Autodesk Fusion 360 part; units mm, degrees
(part 2 of 2)
ref_plane "WorkPlane4" through (0, 0, 1231.63) normal (0, 0, 1) x (1, 0, 0) in component "831001 HARDWARE - LOCATING SPIGOT - M6 X Ø8 - STAINLESS"
sketch "SKETCH - SPIGOT THREAD TOP RAIL SPIGOT HIGH X" plane through (0, 0, 1231.63) normal (0, 0, 1) x (1, 0, 0) in component "831001 HARDWARE - LOCATING SPIGOT - M6 X Ø8 - STAINLESS"
  circle A0 centre (1101.74, 824) radius 3
  dimension "d599" = 1101.74
  dimension "d600" = 824
  dimension "d601" = 6
  measures "d599" horizontal distance of origin A0.centre
  measures "d600" vertical distance of origin A0.centre
  measures "d601" diameter of A0
extrude "EXTRUDE - SPIGOT THREAD TOP RAIL SPIGOT HIGH X" add sketch "SKETCH - SPIGOT THREAD TOP RAIL SPIGOT HIGH X" against normal blind 10 separate body makes body 27 in component "831001 HARDWARE - LOCATING SPIGOT - M6 X Ø8 - STAINLESS"
combine "COMBINE - SPIGOT TOP RAIL SPIGOT HIGH X" operation add target body 26 tool bodies 27 in component "831001 HARDWARE - LOCATING SPIGOT - M6 X Ø8 - STAINLESS"
ref_plane "WorkPlane7" through (2.75, 0, 0) normal (1, 0, 0) x (0, 1, 0) in component "838003 HARDWARE - RIVET NUT - M6 - SHEREX CAH3-610-4.2"
sketch "SKETCH - RIVNUT HEAD CENTRE STILE PIN" plane through (2.75, 0, 0) normal (1, 0, 0) x (0, 0, -1) in component "838003 HARDWARE - RIVET NUT - M6 - SHEREX CAH3-610-4.2"
  circle A0 centre (-332.26, 824) radius 6.48
  circle A1 centre (-332.26, 824) radius 3
  dimension "d608" = 824
  dimension "d609" = 332.26
  dimension "d610" = 12.96
  dimension "d611" = 6
  measures "d608" vertical distance of origin A0.centre
  measures "d609" horizontal distance of origin A0.centre
  measures "d610" diameter of A0
  measures "d611" diameter of A1
extrude "EXTRUDE - RIVNUT HEAD CENTRE STILE PIN" add sketch "SKETCH - RIVNUT HEAD CENTRE STILE PIN" against normal blind 0.76 separate body makes body 28 in component "838003 HARDWARE - RIVET NUT - M6 - SHEREX CAH3-610-4.2"
ref_plane "WorkPlane8" through (2.75, 0, 0) normal (1, 0, 0) x (0, 1, 0) in component "838003 HARDWARE - RIVET NUT - M6 - SHEREX CAH3-610-4.2"
sketch "SKETCH - RIVNUT BODY CENTRE STILE PIN" plane through (2.75, 0, 0) normal (1, 0, 0) x (0, 0, -1) in component "838003 HARDWARE - RIVET NUT - M6 - SHEREX CAH3-610-4.2"
  circle A0 centre (-332.26, 824) radius 4.75
  circle A1 centre (-332.26, 824) radius 3
  dimension "d618" = 824
  dimension "d619" = 332.26
  dimension "d620" = 9.5
  dimension "d621" = 6
  measures "d618" vertical distance of origin A0.centre
  measures "d619" horizontal distance of origin A0.centre
  measures "d620" diameter of A0
  measures "d621" diameter of A1
extrude "EXTRUDE - RIVNUT BODY CENTRE STILE PIN" add sketch "SKETCH - RIVNUT BODY CENTRE STILE PIN" along normal blind 10.16 separate body makes body 29 in component "838003 HARDWARE - RIVET NUT - M6 - SHEREX CAH3-610-4.2"
combine "COMBINE - RIVNUT CENTRE STILE PIN" operation add target body 28 tool bodies 29 in component "838003 HARDWARE - RIVET NUT - M6 - SHEREX CAH3-610-4.2"
pattern_linear "PATTERN - RIVNUT - CENTRE STILE PIN" count 3 spacing 339.305 along (0, 0, 1) of bodies 28 makes body 30 at (9.5233, 828.7131, 670.9744) makes body 31 at (9.5233, 828.7131, 1010.2794) in component "838003 HARDWARE - RIVET NUT - M6 - SHEREX CAH3-610-4.2"
component "211202 WALL - PANEL FRAME - BACK LOWER - B2" placed x (1, 0, 0) y (0, 1, 0) z (0, 0, 1) at (0, 0, 0)
component "211402 WALL - SKIN - BACK LOWER - B2" placed x (1, 0, 0) y (0, 1, 0) z (0, 0, 1) at (0, 0, 0)
component "211602 WALL - CAVITY FILL - BACK LOWER - B2" placed x (1, 0, 0) y (0, 1, 0) z (0, 0, 1) at (0, 0, 0)
component "831002 HARDWARE - STOP WASHER - Ø10.5 X Ø20 X 1.5 - AL" placed x (1, 0, 0) y (0, 1, 0) z (0, 0, 1) at (0, 0, 0)
component "838003 HARDWARE - RIVET NUT - M6 - SHEREX CAH3-610-4.2" placed x (1, 0, 0) y (0, 1, 0) z (0, 0, 1) at (0, 0, 0)
component "831001 HARDWARE - LOCATING SPIGOT - M6 X Ø8 - STAINLESS" placed x (1, 0, 0) y (0, 1, 0) z (0, 0, 1) at (0, 0, 0)
equation "pod_w_Ref = 2500 mm" comment "DECIDED: D-01; conventions s4 (X = +-1250)"
equation "pod_d_Ref = 1700 mm" comment "DECIDED: D-01; conventions s4 (Y = +-850)"
equation "pod_h_Ref = 2400 mm" comment "DECIDED: D-21 (room floor to roof skin top)"
equation "glide_h_Ref = 10 mm" comment "ASSUMPTION: layout study inputs.py glide_h"
equation "band_h_Ref = 100 mm" comment "SOURCE: layout study B1 list B-BAND 100x40; inputs.py base_h"
equation "outer_t_Ref = skin_t_Ref + bond_t_Ref + frame_t_Ref" comment "DECIDED: PM ruling 2026-10-31: ACP 3 + bond line 3 + frame 40, walls and ceiling (was 43)"
equation "cav_gap_Ref = 4 mm" comment "DECIDED: D-16, D-42: the gap between the outer panel and the lining cassette in the wall and ceiling stack"
equation "cass_t_Ref = 34 mm" comment "SOURCE: layout study B1 final list L-CASS 34 (tray + 25 gap + felt 9)"
equation "stack_t_Ref = outer_t_Ref + cav_gap_Ref + cass_t_Ref" comment "CALCULATION: D-16, D-42 stack, walls and ceiling: outer panel + cavity gap + cassette (PM ruling 2026-10-31 on outer_t)"
equation "lin_gap_Ref = 4 mm" comment "ASSUMPTION: PM ruling pass C: gap above the upper side linings so they stay floating (= the 4 mm stack gap)"
equation "seam_gap_Ref = 2.26 mm" comment "DECIDED: PM ruling 2026-10-31 (Mechanical Checker F-001, F-005): the Joints Engineer's 2.26 mm at all nine site seam types, set by a metal stop (1.5 stop washer + 0.76 rivnut head; joints register section 2.8)"
equation "wall_z0_Ref = glide_h_Ref + band_h_Ref" comment "CALCULATION: base band top: glides + band"
equation "panel_z0_Ref = wall_z0_Ref + seam_gap_Ref" comment "CALCULATION: walls stand one seam_gap above the band top (joints register 2.8, IF-01)"
equation "back_oh_Ref = pod_h_Ref - outer_t_Ref - seam_gap_Ref - panel_z0_Ref" comment "CALCULATION: PM ruling 2026-10-31 (pass D, F-004): the back outer frames run up to the ceiling frame (pod_h - outer_t), less the seam_gap under it, closing the slot at the back top edge"
equation "back_ph_Ref = ( back_oh_Ref - seam_gap_Ref ) / 2" comment "CALCULATION: D-23: 4 sheets on the back, two equal rows with one seam_gap between them (joints register 2.8); the lower back linings match the lower row, as on the side walls"
equation "half_pw_Ref = ( pod_w_Ref - 2 * outer_t_Ref - 3 * seam_gap_Ref ) / 2" comment "CALCULATION: SKIN width of each back and ceiling panel: two skins and three seam_gap seams between the side frames (F-001, joints register 2.8)"
equation "n_base_bolt_Ref = 4" comment "DECIDED: PM ruling 2026-10-31, J-BASE-01: bolts per panel along the band, evenly spaced"
equation "skin_t_Ref = 3 mm" comment "DECIDED: ACP skin, walls and ceiling (D-16; PM ruling 2026-10-31 on outer_t)"
equation "bond_t_Ref = 3 mm" comment "DECIDED: bond line between the ACP and the frame (PM ruling 2026-10-31 on outer_t)"
equation "frame_t_Ref = 40 mm" comment "DECIDED: aluminium frame tube depth, walls and ceiling (PM ruling 2026-10-31 on outer_t)"
equation "close_gap_Ref = 5.5 mm" comment "DECIDED: PM ruling 2026-10-31 (joints register, F-011/F-012): frame gap at the closing seams B1-B2, B3-B4 and C1-C2, which have no hard stop (slotted holes, thicker gasket)"
equation "half_fw_Ref = ( pod_w_Ref - 2 * outer_t_Ref - 2 * seam_gap_Ref - close_gap_Ref ) / 2" comment "CALCULATION: FRAME width of each back and ceiling panel: the skins overhang their frames by half_pw - half_fw at the closing seam (PM ruling 2026-10-31)"
equation "bolt_edge_inset_Ref = 220 mm" comment "DECIDED: PM ruling 2026-10-31: on every bolted edge the end bolts sit this far in from each panel end (the FRAME end, where the bolts go), the rest evenly spaced"
equation "spigot_inset_Ref = 100 mm" comment "DECIDED: PM ruling 2026-10-31: locating spigots this far in from each panel end (round hole at one end, slot at the other)"
equation "pod_w = pod_w_Ref" comment "LINKED: pod_w_Ref, derived from 100000_P04_POD-SKELETON_CAD v4 (skeleton is the single source)"
equation "pod_d = pod_d_Ref" comment "LINKED: pod_d_Ref, derived from 100000_P04_POD-SKELETON_CAD v4 (skeleton is the single source)"
equation "pod_h = pod_h_Ref" comment "LINKED: pod_h_Ref, derived from 100000_P04_POD-SKELETON_CAD v4 (skeleton is the single source)"
equation "panel_z0 = panel_z0_Ref" comment "LINKED: panel_z0_Ref, derived from 100000_P04_POD-SKELETON_CAD v4 (skeleton is the single source)"
equation "back_ph = back_ph_Ref" comment "LINKED: back_ph_Ref, derived from 100000_P04_POD-SKELETON_CAD v4 (skeleton is the single source)"
equation "back_oh = back_oh_Ref" comment "LINKED: back_oh_Ref, derived from 100000_P04_POD-SKELETON_CAD v4 (skeleton is the single source)"
equation "half_pw = half_pw_Ref" comment "LINKED: half_pw_Ref, derived from 100000_P04_POD-SKELETON_CAD v4 (skeleton is the single source)"
equation "half_fw = half_fw_Ref" comment "LINKED: half_fw_Ref, derived from 100000_P04_POD-SKELETON_CAD v4 (skeleton is the single source)"
equation "close_gap = close_gap_Ref" comment "LINKED: close_gap_Ref, derived from 100000_P04_POD-SKELETON_CAD v4 (skeleton is the single source)"
equation "stack_t = stack_t_Ref" comment "LINKED: stack_t_Ref, derived from 100000_P04_POD-SKELETON_CAD v4 (skeleton is the single source)"
equation "outer_t = outer_t_Ref" comment "LINKED: outer_t_Ref, derived from 100000_P04_POD-SKELETON_CAD v4 (skeleton is the single source)"
equation "cass_t = cass_t_Ref" comment "LINKED: cass_t_Ref, derived from 100000_P04_POD-SKELETON_CAD v4 (skeleton is the single source)"
equation "lin_gap = lin_gap_Ref" comment "LINKED: lin_gap_Ref, derived from 100000_P04_POD-SKELETON_CAD v4 (skeleton is the single source)"
equation "seam_gap = seam_gap_Ref" comment "LINKED: seam_gap_Ref, derived from 100000_P04_POD-SKELETON_CAD v4 (skeleton is the single source)"
equation "skin_t = skin_t_Ref" comment "LINKED: skin_t_Ref, derived from 100000_P04_POD-SKELETON_CAD v4 (skeleton is the single source)"
equation "bond_t = bond_t_Ref" comment "LINKED: bond_t_Ref, derived from 100000_P04_POD-SKELETON_CAD v4 (skeleton is the single source)"
equation "bolt_edge_inset = bolt_edge_inset_Ref" comment "LINKED: bolt_edge_inset_Ref, derived from 100000_P04_POD-SKELETON_CAD v4 (skeleton is the single source)"
equation "spigot_inset = spigot_inset_Ref" comment "LINKED: spigot_inset_Ref, derived from 100000_P04_POD-SKELETON_CAD v4 (skeleton is the single source)"
equation "n_base_bolt = n_base_bolt_Ref" comment "LINKED: n_base_bolt_Ref, derived from 100000_P04_POD-SKELETON_CAD v4 (skeleton is the single source)"
equation "tube_w = 20 mm" comment "CONFIRMED: D-34, D-54: aluminium tube 20 x 40 x 1.2; the 20 mm face carries the skin, so the 40 mm runs through the wall (outer_t = ACP 3 + frame 40). The joint register may turn it for the bond width (HOLD)"
equation "tube_d = outer_t - skin_t - bond_t" comment "CALCULATION: frame depth = outer panel 46 - skin 3 - bond 3 = 40 (D-34)"
equation "tube_t = 1.2 mm" comment "CONFIRMED: D-34, D-54, D-85: perimeter members (rails, front and back stiles) keep the 1.2 mm wall; they carry the rivnuts (grip check passed)"
equation "stud_t = 1.0 mm" comment "CONFIRMED: D-85 (weight): intermediate studs at a 1.0 mm wall; they carry no rivnut, only the skin's bond line"
equation "stile_pitch_max = 400 mm" comment "CONFIRMED: D-16, D-34: members 400 mm apart or less, to keep the ACP flat"
equation "skin_setback = 0 mm" comment "ASSUMPTION: skin edge set back from the frame's top and bottom edges: 0, so the outside reveal equals the 2.26 seam gap (D-23: crisp, aligned reveals; joints register 2.8 leaves the setback to the WALL drawing)"
equation "fill_t = tube_d" comment "CALCULATION: 40 mm PET fill fills the frame depth (D-34; layout study 40 mm)"
equation "bolt_d = 7 mm" comment "CONFIRMED: PM ruling on F-009: bolt holes 7.0 (0.51 float), position tolerance 0.4 (+-0.2) from the spigot hole, CNC or drill jig (joints register FR-02)"
equation "access_d = 19 mm" comment "CALCULATION: register FR-03: passes the 18 mm head washer (ISO 7093-1, R-J10), the M6 head and the 5 mm key; holds the grommet retainer (H-02)"
equation "bolt_line_y = pod_d / 2 - skin_t - bond_t - tube_d / 2" comment "CONFIRMED: J-WALL-02 bolt line on the back panel's tube centre, Y 824 (joints register R-J15, FR-07)"
equation "rivnut_d = 9.53 mm" comment "SOURCE: Sherex CAH3-610-4.2 hole 9.53 +0.10 (HW-SEL A5; register H-03)"
equation "spigot_d = 8.5 mm" comment "ASSUMPTION: register FR-05: hole for the 8 mm locating spigot H-05"
equation "spigot_slot = 14 mm" comment "ASSUMPTION: register FR-05: slot length for the second spigot"
equation "spigot_edge = spigot_inset" comment "CALCULATION: the skeleton's spigot_inset: spigots 100 from each end of the edge (PM ruling 2026-10-31, R-J13)"
equation "bolt_edge = bolt_edge_inset" comment "CALCULATION: the skeleton's bolt_edge_inset: end bolts 220 in from the panel's ends, evenly spaced, every bolt 30 or more from any stile (PM ruling 2026-10-31, R-J14)"
equation "pocket_w = 60 mm" comment "ASSUMPTION: register FR-10: fill left out 60 x 60 next to each bolt for the key"
equation "felt_t = 9 mm" comment "SOURCE: plan VT03-PET 9 mm PET felt; HW-SEL A3; D-31 (the factory's felt)"
equation "tray_t = 0.5 mm" comment "CONFIRMED: D-37: galvanised steel tray 0.5 mm"
equation "tray_h = cass_t" comment "CONFIRMED: PM ruling 2026-10-31 (WALL group, option 1): the wall cassettes use the ceiling's tray, returns the full cassette depth (34) turned in as lips that hold the felt, no ribs; settles H09 for the walls"
equation "lip_w = 12 mm" comment "CONFIRMED: PM ruling 2026-10-31 (WALL group, option 1): 12 mm lips hold the felt edge"
equation "bend_r = tray_t" comment "ASSUMPTION: inside bend radius 1 x t for 0.5 mm DX51D (the sheet metal rule's bend radius is its Thickness); the factory's tooling sets it (guideline 9)"
equation "felt_c = 1 mm" comment "ASSUMPTION: felt edge clearance inside the returns, as the ceiling cassette"
equation "gap_h = tray_h - felt_t - 2 * tray_t" comment "CALCULATION: air gap between the tray base and the felt (24): the acoustic gap (D-17) and the cable path (D-26)"
equation "clip_zone_h = 60 mm" comment "ASSUMPTION: height of each reserved clip zone (H03: no clip named)"
equation "clip_zone_dz = 100 mm" comment "ASSUMPTION: clip zone centre from the cassette's top and bottom edges (H03)"
equation "stopw_od = 20 mm" comment "SOURCE: joints register H-08: stop washer Ø10.5 x Ø20 x 1.5 (PROPOSED part)"
equation "stopw_id = 10.5 mm" comment "SOURCE: joints register H-08"
equation "stopw_t = 1.5 mm" comment "SOURCE: joints register H-08: rivnut head 0.76 + washer 1.5 = the 2.26 stop (R-J5)"
equation "rivnut_head_d = 12.96 mm" comment "SOURCE: Sherex CAH3-610-4.2 head Ø12.96 (joints register H-03, SHX)"
equation "rivnut_head_t = 0.76 mm" comment "SOURCE: Sherex CAH3-610-4.2 head 0.76 ±0.08 (H-03, SHX)"
equation "rivnut_body_d = 9.5 mm" comment "SOURCE: Sherex CAH3-610-4.2 body Ø9.50 max (H-03, SHX)"
equation "rivnut_len = 10.16 mm" comment "SOURCE: Sherex CAH3-610-4.2 installed length 10.16 max under the head (H-03, SHX); the bulge inside the tube is not modelled"
equation "m6_d = 6 mm" comment "CALCULATION: M6 threads shown at their 6 mm major diameter (no modelled thread)"
equation "spigot_pin_d = 8 mm" comment "SOURCE: joints register H-05: Ø8 stainless pin (PROPOSED, assumption sizes)"
equation "spigot_proud = 8 mm" comment "SOURCE: joints register H-05: stands 8 proud (read as: of the joint face)"
equation "spigot_thread_l = 10 mm" comment "ASSUMPTION: M6 thread into the spigot rivnut; H-05 gives no length; 10 stays inside the rivnut's 10.16"
equation "lead_in = 1 mm" comment "SOURCE: joints register 2.10 (R-J9): 1 x 45 degree lead-in on the top edge of each closing-seam face, so the panel beside it drops in past it without catching the bulb seal"
equation "pnl_len = half_pw" comment "CALCULATION: skeleton half_pw: the back panel's skin width (1200.61 on P04)"
equation "frm_len = half_fw" comment "CALCULATION: the skeleton's half_fw, 1198.99: the frame stops close_gap / 2 from X 0 and 1.62 short of its skin (R-J16)"
equation "pnl_h = back_ph" comment "CALCULATION: skeleton back row height (1118.61 on P04)"
equation "frm_h = pnl_h" comment "CALCULATION: the frame fills the row height; the seam gaps are outside it (P04)"
equation "top_h = tube_w" comment "CALCULATION: the back panels' top rails stay 20 x 40 (the ceiling's back member is the 40 x 40, R-J3)"
equation "stile_n_mid = ceil(( frm_len - tube_w ) / stile_pitch_max) - 1" comment "CALCULATION: intermediate stiles so that no stile pitch exceeds stile_pitch_max"
equation "stile_pitch = ( frm_len - tube_w ) / ( stile_n_mid + 1 )" comment "CALCULATION: equal stile pitch, centre to centre"
equation "stile_len = frm_h - 2 * tube_w" comment "CALCULATION: stiles between the full-width rails (butt joints)"
equation "n_len_bolt = n_base_bolt" comment "CALCULATION: the skeleton's n_base_bolt (4): also on the horizontal seam and the ceiling back edge (register 2.9; the skeleton's n_ceil_back_bolt 3 is an old assumption, flagged)"
equation "len_bolt_pitch = ( frm_len - 2 * bolt_edge ) / ( n_len_bolt - 1 )" comment "CALCULATION: 253.00 on P04: 220, 473.00, 725.99, 978.99 from the frame's ends (register 2.9; the skeleton's back_base_pitch uses the 1200.61 skin and gives 253.54, flagged to its owner)"
equation "n_side_jnt = 3" comment "SOURCE: 3 bolts on the back corner and on the closing seam (register 2.9)"
equation "side_jnt_pitch = ( pnl_h - 2 * bolt_edge ) / ( n_side_jnt - 1 )" comment "CALCULATION: 339.31 on P04: 220, 559.31, 898.61 up the 1118.61 edge (register 2.9)"
equation "cass_len = pod_w / 2 - stack_t - seam_gap / 2" comment "ASSUMPTION: PROPOSED (WALL): from the side lining's face to seam_gap / 2 short of X 0. Each cassette hangs on its own panel's frame and the closing seam moves (5.2 to 5.8, register 2.11), so the skeleton's touching edges at X 0 could clash; a 2.26 gap matches the skin seam above it (R-J16) and takes the H-14 edge seal"
equation "cass_h = pnl_h" comment "CALCULATION: lower: the row height; upper: up to lin_gap under the ceiling frame, floating (D-57; P04)"
equation "el_pu_x0 = 95 mm" comment "ASSUMPTION: ELECTRICAL P01 (electrical_model.py, PR #64) pu_x0: the power unit's left side, clear of the closing seam member and its pin-bolt pocket"
equation "el_pu_h = 260 mm" comment "SOURCE: ELECTRICAL's final unit size (PM 2026-10-31 20:38 UTC): Z 870 to 1130"
equation "el_pu_zc = 1000 mm" comment "CONFIRMED: ELECTRICAL P01 (electrical_model.py, PR #64) pu_zc: the socket and LAN at the ledge height (D-70)"
equation "el_pu_clr = 4 mm" comment "ASSUMPTION: ELECTRICAL P01 (electrical_model.py, PR #64) pu_clr: the gap round the frame-mounted unit, so the cassette stays floating (= cav_gap)"
equation "el_cut_x0 = el_pu_x0 - el_pu_clr" comment "CALCULATION: B2-CASS cut-out: its left return's inner face (X 91)"
equation "el_cut_z0 = el_pu_zc - el_pu_h / 2 - el_pu_clr" comment "CALCULATION: B2-CASS cut-out: its bottom return's inner face (Z 866)"
equation "el_cut_z1 = el_pu_zc + el_pu_h / 2 + el_pu_clr" comment "CALCULATION: ELECTRICAL P01 (electrical_model.py, PR #64) cut_z1: B2-CASS cut-out: its top return's inner face (Z 1134)"
equation "el_inlet_x = 120 mm" comment "ASSUMPTION: ELECTRICAL P01 (electrical_model.py, PR #64) inlet_x: the inlet column, just clear of the closing seam"
equation "el_inlet_z = 313 mm" comment "SOURCE: ELECTRICAL P01 (electrical_model.py, PR #64) inlet_z: v1's 'Power Jack' centre Z 298.3 + 15"
equation "el_lan_z = 375 mm" comment "SOURCE: ELECTRICAL P01 (electrical_model.py, PR #64) lan_z: v1's 'Jack LAN' centre Z 360 + 15"
equation "el_inlet_d = 24 mm" comment "SOURCE: ELECTRICAL P01 (electrical_model.py, PR #64) inlet_d: powerCON TRUE1 TOP cut-out 23.8, etherCON NE8FDP 24"
equation "el_sl_x = el_inlet_x + 30 mm" comment "CALCULATION: ELECTRICAL P01 (electrical_model.py, PR #64) sl_x: the mains and LAN sleeve's centre (X 150)"
equation "el_sl_w = 20 mm" comment "ASSUMPTION: ELECTRICAL P01 (electrical_model.py, PR #64) SLEEVE: the sleeve's 20 x 20 envelope"
equation "d173 = panel_z0"
equation "d175 = ( close_gap / 2 + half_fw ) - ( close_gap / 2 )"
equation "d176 = ( pod_d / 2 - skin_t - bond_t ) - ( pod_d / 2 - outer_t )"
equation "d177 = abs(close_gap / 2)"
equation "d178 = abs(pod_d / 2 - outer_t)"
equation "d179 = ( ( panel_z0 ) + tube_w ) - ( panel_z0 )"
equation "d181 = ( panel_z0 ) + tube_t"
equation "d183 = ( close_gap / 2 + half_fw ) - ( close_gap / 2 )"
equation "d184 = ( ( pod_d / 2 - skin_t - bond_t ) - tube_t ) - ( ( pod_d / 2 - outer_t ) + tube_t )"
equation "d185 = abs(close_gap / 2)"
equation "d186 = abs(( pod_d / 2 - outer_t ) + tube_t)"
equation "d187 = ( ( ( panel_z0 ) + tube_w ) - tube_t ) - ( ( panel_z0 ) + tube_t )"
equation "d189 = ( panel_z0 + back_ph ) - top_h"
equation "d191 = ( close_gap / 2 + half_fw ) - ( close_gap / 2 )"
equation "d192 = ( pod_d / 2 - skin_t - bond_t ) - ( pod_d / 2 - outer_t )"
equation "d193 = abs(close_gap / 2)"
equation "d194 = abs(pod_d / 2 - outer_t)"
equation "d195 = ( panel_z0 + back_ph ) - ( ( panel_z0 + back_ph ) - top_h )"
equation "d197 = ( ( panel_z0 + back_ph ) - top_h ) + tube_t"
equation "d199 = ( close_gap / 2 + half_fw ) - ( close_gap / 2 )"
equation "d200 = ( ( pod_d / 2 - skin_t - bond_t ) - tube_t ) - ( ( pod_d / 2 - outer_t ) + tube_t )"
equation "d201 = abs(close_gap / 2)"
equation "d202 = abs(( pod_d / 2 - outer_t ) + tube_t)"
equation "d203 = ( ( panel_z0 + back_ph ) - tube_t ) - ( ( ( panel_z0 + back_ph ) - top_h ) + tube_t )"
equation "d205 = ( panel_z0 ) + tube_w"
equation "d207 = ( ( close_gap / 2 ) + tube_w ) - ( close_gap / 2 )"
equation "d208 = ( pod_d / 2 - skin_t - bond_t ) - ( pod_d / 2 - outer_t )"
equation "d209 = abs(close_gap / 2)"
equation "d210 = abs(pod_d / 2 - outer_t)"
equation "d211 = ( ( panel_z0 + back_ph ) - top_h ) - ( ( panel_z0 ) + tube_w )"
equation "d213 = ( panel_z0 ) + tube_w"
equation "d215 = ( ( ( close_gap / 2 ) + tube_w ) - tube_t ) - ( ( close_gap / 2 ) + tube_t )"
equation "d216 = ( ( pod_d / 2 - skin_t - bond_t ) - tube_t ) - ( ( pod_d / 2 - outer_t ) + tube_t )"
equation "d217 = abs(( close_gap / 2 ) + tube_t)"
equation "d218 = abs(( pod_d / 2 - outer_t ) + tube_t)"
equation "d219 = ( ( panel_z0 + back_ph ) - top_h ) - ( ( panel_z0 ) + tube_w )"
equation "d221 = ( panel_z0 ) + tube_w"
equation "d223 = ( close_gap / 2 + half_fw ) - ( ( close_gap / 2 + half_fw ) - tube_w )"
equation "d224 = ( pod_d / 2 - skin_t - bond_t ) - ( pod_d / 2 - outer_t )"
equation "d225 = abs(( close_gap / 2 + half_fw ) - tube_w)"
equation "d226 = abs(pod_d / 2 - outer_t)"
equation "d227 = ( ( panel_z0 + back_ph ) - top_h ) - ( ( panel_z0 ) + tube_w )"
equation "d229 = ( panel_z0 ) + tube_w"
equation "d231 = ( ( close_gap / 2 + half_fw ) - tube_t ) - ( ( ( close_gap / 2 + half_fw ) - tube_w ) + tube_t )"
equation "d232 = ( ( pod_d / 2 - skin_t - bond_t ) - tube_t ) - ( ( pod_d / 2 - outer_t ) + tube_t )"
equation "d233 = abs(( ( close_gap / 2 + half_fw ) - tube_w ) + tube_t)"
equation "d234 = abs(( pod_d / 2 - outer_t ) + tube_t)"
equation "d235 = ( ( panel_z0 + back_ph ) - top_h ) - ( ( panel_z0 ) + tube_w )"
equation "d237 = ( panel_z0 ) + tube_w"
equation "d239 = ( ( close_gap / 2 ) + stile_pitch + tube_w ) - ( ( close_gap / 2 ) + stile_pitch )"
equation "d240 = ( pod_d / 2 - skin_t - bond_t ) - ( pod_d / 2 - outer_t )"
equation "d241 = abs(( close_gap / 2 ) + stile_pitch)"
equation "d242 = abs(pod_d / 2 - outer_t)"
equation "d243 = ( ( panel_z0 + back_ph ) - top_h ) - ( ( panel_z0 ) + tube_w )"
equation "d245 = ( panel_z0 ) + tube_w"
equation "d247 = ( ( ( close_gap / 2 ) + stile_pitch + tube_w ) - stud_t ) - ( ( ( close_gap / 2 ) + stile_pitch ) + stud_t )"
equation "d248 = ( ( pod_d / 2 - skin_t - bond_t ) - stud_t ) - ( ( pod_d / 2 - outer_t ) + stud_t )"
equation "d249 = abs(( ( close_gap / 2 ) + stile_pitch ) + stud_t)"
equation "d250 = abs(( pod_d / 2 - outer_t ) + stud_t)"
equation "d251 = ( ( panel_z0 + back_ph ) - top_h ) - ( ( panel_z0 ) + tube_w )"
equation "d253 = stile_n_mid"
equation "d255 = stile_pitch"
equation "d257 = ( panel_z0 ) + skin_setback"
equation "d259 = ( seam_gap / 2 + half_pw ) - ( seam_gap / 2 )"
equation "d260 = ( pod_d / 2 ) - ( pod_d / 2 - skin_t )"
equation "d261 = abs(seam_gap / 2)"
equation "d262 = abs(pod_d / 2 - skin_t)"
equation "d263 = ( ( panel_z0 + back_ph ) - skin_setback ) - ( ( panel_z0 ) + skin_setback )"
equation "d265 = pod_d / 2"
equation "d267 = abs(el_inlet_x)"
equation "d268 = abs(el_inlet_z)"
equation "d269 = skin_t + 1 mm"
equation "d270 = el_inlet_d"
equation "d272 = pod_d / 2"
equation "d274 = abs(el_inlet_x)"
equation "d275 = abs(el_lan_z)"
equation "d276 = skin_t + 1 mm"
equation "d277 = el_inlet_d"
equation "d279 = ( panel_z0 ) + tube_w"
equation "d281 = ( ( close_gap / 2 ) + stile_pitch ) - ( ( close_gap / 2 ) + tube_w )"
equation "d282 = ( pod_d / 2 - skin_t - bond_t ) - ( pod_d / 2 - outer_t )"
equation "d283 = abs(( close_gap / 2 ) + tube_w)"
equation "d284 = abs(pod_d / 2 - outer_t)"
equation "d285 = ( ( panel_z0 + back_ph ) - top_h ) - ( ( panel_z0 ) + tube_w )"
equation "d287 = stile_n_mid + 1"
equation "d289 = stile_pitch"
equation "d291 = ( panel_z0 ) + tube_w"
equation "d293 = ( ( ( close_gap / 2 ) + bolt_edge + 0 * len_bolt_pitch ) + pocket_w / 2 ) - ( ( ( close_gap / 2 ) + bolt_edge + 0 * len_bolt_pitch ) - pocket_w / 2 )"
equation "d294 = ( pod_d / 2 - skin_t - bond_t ) - ( pod_d / 2 - outer_t )"
equation "d295 = abs(( ( close_gap / 2 ) + bolt_edge + 0 * len_bolt_pitch ) - pocket_w / 2)"
equation "d296 = abs(pod_d / 2 - outer_t)"
equation "d297 = ( ( ( panel_z0 ) + tube_w ) + pocket_w ) - ( ( panel_z0 ) + tube_w )"
equation "d299 = ( panel_z0 ) + tube_w"
equation "d301 = ( ( ( close_gap / 2 ) + bolt_edge + 1 * len_bolt_pitch ) + pocket_w / 2 ) - ( ( ( close_gap / 2 ) + bolt_edge + 1 * len_bolt_pitch ) - pocket_w / 2 )"
equation "d302 = ( pod_d / 2 - skin_t - bond_t ) - ( pod_d / 2 - outer_t )"
equation "d303 = abs(( ( close_gap / 2 ) + bolt_edge + 1 * len_bolt_pitch ) - pocket_w / 2)"
equation "d304 = abs(pod_d / 2 - outer_t)"
equation "d305 = ( ( ( panel_z0 ) + tube_w ) + pocket_w ) - ( ( panel_z0 ) + tube_w )"
equation "d307 = ( panel_z0 ) + tube_w"
equation "d309 = ( ( ( close_gap / 2 ) + bolt_edge + 2 * len_bolt_pitch ) + pocket_w / 2 ) - ( ( ( close_gap / 2 ) + bolt_edge + 2 * len_bolt_pitch ) - pocket_w / 2 )"
equation "d310 = ( pod_d / 2 - skin_t - bond_t ) - ( pod_d / 2 - outer_t )"
equation "d311 = abs(( ( close_gap / 2 ) + bolt_edge + 2 * len_bolt_pitch ) - pocket_w / 2)"
equation "d312 = abs(pod_d / 2 - outer_t)"
equation "d313 = ( ( ( panel_z0 ) + tube_w ) + pocket_w ) - ( ( panel_z0 ) + tube_w )"
equation "d315 = ( panel_z0 ) + tube_w"
equation "d317 = ( ( ( close_gap / 2 ) + bolt_edge + 3 * len_bolt_pitch ) + pocket_w / 2 ) - ( ( ( close_gap / 2 ) + bolt_edge + 3 * len_bolt_pitch ) - pocket_w / 2 )"
equation "d318 = ( pod_d / 2 - skin_t - bond_t ) - ( pod_d / 2 - outer_t )"
equation "d319 = abs(( ( close_gap / 2 ) + bolt_edge + 3 * len_bolt_pitch ) - pocket_w / 2)"
equation "d320 = abs(pod_d / 2 - outer_t)"
equation "d321 = ( ( ( panel_z0 ) + tube_w ) + pocket_w ) - ( ( panel_z0 ) + tube_w )"
equation "d323 = ( ( panel_z0 ) + bolt_edge + 0 * side_jnt_pitch ) - pocket_w / 2"
equation "d325 = ( ( close_gap / 2 + half_fw ) + -1 * tube_w ) - ( ( ( close_gap / 2 + half_fw ) + -1 * tube_w ) - pocket_w )"
equation "d326 = ( pod_d / 2 - skin_t - bond_t ) - ( pod_d / 2 - outer_t )"
equation "d327 = abs(( ( close_gap / 2 + half_fw ) + -1 * tube_w ) - pocket_w)"
equation "d328 = abs(pod_d / 2 - outer_t)"
equation "d329 = ( ( ( panel_z0 ) + bolt_edge + 0 * side_jnt_pitch ) + pocket_w / 2 ) - ( ( ( panel_z0 ) + bolt_edge + 0 * side_jnt_pitch ) - pocket_w / 2 )"
equation "d331 = ( ( panel_z0 ) + bolt_edge + 1 * side_jnt_pitch ) - pocket_w / 2"
equation "d333 = ( ( close_gap / 2 + half_fw ) + -1 * tube_w ) - ( ( ( close_gap / 2 + half_fw ) + -1 * tube_w ) - pocket_w )"
equation "d334 = ( pod_d / 2 - skin_t - bond_t ) - ( pod_d / 2 - outer_t )"
equation "d335 = abs(( ( close_gap / 2 + half_fw ) + -1 * tube_w ) - pocket_w)"
equation "d336 = abs(pod_d / 2 - outer_t)"
equation "d337 = ( ( ( panel_z0 ) + bolt_edge + 1 * side_jnt_pitch ) + pocket_w / 2 ) - ( ( ( panel_z0 ) + bolt_edge + 1 * side_jnt_pitch ) - pocket_w / 2 )"
equation "d339 = ( ( panel_z0 ) + bolt_edge + 2 * side_jnt_pitch ) - pocket_w / 2"
equation "d341 = ( ( close_gap / 2 + half_fw ) + -1 * tube_w ) - ( ( ( close_gap / 2 + half_fw ) + -1 * tube_w ) - pocket_w )"
equation "d342 = ( pod_d / 2 - skin_t - bond_t ) - ( pod_d / 2 - outer_t )"
equation "d343 = abs(( ( close_gap / 2 + half_fw ) + -1 * tube_w ) - pocket_w)"
equation "d344 = abs(pod_d / 2 - outer_t)"
equation "d345 = ( ( ( panel_z0 ) + bolt_edge + 2 * side_jnt_pitch ) + pocket_w / 2 ) - ( ( ( panel_z0 ) + bolt_edge + 2 * side_jnt_pitch ) - pocket_w / 2 )"
equation "d347 = ( ( panel_z0 ) + bolt_edge + 0 * side_jnt_pitch ) - pocket_w / 2"
equation "d349 = ( ( ( close_gap / 2 ) + 1 * tube_w ) + pocket_w ) - ( ( close_gap / 2 ) + 1 * tube_w )"
equation "d350 = ( pod_d / 2 - skin_t - bond_t ) - ( pod_d / 2 - outer_t )"
equation "d351 = abs(( close_gap / 2 ) + 1 * tube_w)"
equation "d352 = abs(pod_d / 2 - outer_t)"
equation "d353 = ( ( ( panel_z0 ) + bolt_edge + 0 * side_jnt_pitch ) + pocket_w / 2 ) - ( ( ( panel_z0 ) + bolt_edge + 0 * side_jnt_pitch ) - pocket_w / 2 )"
equation "d355 = ( ( panel_z0 ) + bolt_edge + 1 * side_jnt_pitch ) - pocket_w / 2"
equation "d357 = ( ( ( close_gap / 2 ) + 1 * tube_w ) + pocket_w ) - ( ( close_gap / 2 ) + 1 * tube_w )"
equation "d358 = ( pod_d / 2 - skin_t - bond_t ) - ( pod_d / 2 - outer_t )"
equation "d359 = abs(( close_gap / 2 ) + 1 * tube_w)"
equation "d360 = abs(pod_d / 2 - outer_t)"
equation "d361 = ( ( ( panel_z0 ) + bolt_edge + 1 * side_jnt_pitch ) + pocket_w / 2 ) - ( ( ( panel_z0 ) + bolt_edge + 1 * side_jnt_pitch ) - pocket_w / 2 )"
equation "d363 = ( ( panel_z0 ) + bolt_edge + 2 * side_jnt_pitch ) - pocket_w / 2"
equation "d365 = ( ( ( close_gap / 2 ) + 1 * tube_w ) + pocket_w ) - ( ( close_gap / 2 ) + 1 * tube_w )"
equation "d366 = ( pod_d / 2 - skin_t - bond_t ) - ( pod_d / 2 - outer_t )"
equation "d367 = abs(( close_gap / 2 ) + 1 * tube_w)"
equation "d368 = abs(pod_d / 2 - outer_t)"
equation "d369 = ( ( ( panel_z0 ) + bolt_edge + 2 * side_jnt_pitch ) + pocket_w / 2 ) - ( ( ( panel_z0 ) + bolt_edge + 2 * side_jnt_pitch ) - pocket_w / 2 )"
equation "d371 = el_cut_z0"
equation "d373 = ( ( close_gap / 2 ) + stile_pitch + tube_w / 2 ) - ( el_cut_x0 )"
equation "d374 = ( ( pod_d / 2 - skin_t - bond_t ) + 1 mm ) - ( ( pod_d / 2 - outer_t ) - 1 mm )"
equation "d375 = abs(el_cut_x0)"
equation "d376 = abs(( pod_d / 2 - outer_t ) - 1 mm)"
equation "d377 = ( el_cut_z1 ) - ( el_cut_z0 )"
equation "d379 = el_inlet_z - el_inlet_d / 2"
equation "d381 = ( el_sl_x + el_sl_w / 2 ) - ( el_sl_x - el_sl_w / 2 )"
equation "d382 = ( ( pod_d / 2 - skin_t - bond_t ) + 1 mm ) - ( ( pod_d / 2 - outer_t ) - 1 mm )"
equation "d383 = abs(el_sl_x - el_sl_w / 2)"
equation "d384 = abs(( pod_d / 2 - outer_t ) - 1 mm)"
equation "d385 = ( el_cut_z0 ) - ( el_inlet_z - el_inlet_d / 2 )"
equation "d387 = el_inlet_z - el_inlet_d / 2"
equation "d389 = ( el_sl_x + el_sl_w / 2 ) - ( el_inlet_x - el_inlet_d / 2 )"
equation "d390 = ( ( pod_d / 2 - skin_t - bond_t ) + 1 mm ) - ( ( pod_d / 2 - outer_t ) - 1 mm )"
equation "d391 = abs(el_inlet_x - el_inlet_d / 2)"
equation "d392 = abs(( pod_d / 2 - outer_t ) - 1 mm)"
equation "d393 = ( el_lan_z + el_inlet_d / 2 ) - ( el_inlet_z - el_inlet_d / 2 )"
equation "d395 = panel_z0"
equation "d397 = abs(( close_gap / 2 ) + bolt_edge)"
equation "d398 = abs(pod_d / 2 - skin_t - bond_t - tube_d / 2)"
equation "d399 = tube_t"
equation "d400 = bolt_d"
equation "d402 = ( panel_z0 ) + tube_w"
equation "d404 = abs(( close_gap / 2 ) + bolt_edge)"
equation "d405 = abs(pod_d / 2 - skin_t - bond_t - tube_d / 2)"
equation "d406 = tube_t"
equation "d407 = access_d"
equation "d409 = n_len_bolt"
equation "d411 = len_bolt_pitch"
equation "d413 = panel_z0"
equation "d415 = abs(( close_gap / 2 ) - -1 * spigot_edge)"
equation "d416 = abs(pod_d / 2 - skin_t - bond_t - tube_d / 2)"
equation "d417 = tube_t"
equation "d418 = spigot_d"
equation "d420 = panel_z0"
equation "d422 = ( ( ( close_gap / 2 + half_fw ) + -1 * spigot_edge ) + ( spigot_slot - spigot_d ) / 2 ) - ( ( ( close_gap / 2 + half_fw ) + -1 * spigot_edge ) - ( spigot_slot - spigot_d ) / 2 )"
equation "d423 = ( ( pod_d / 2 - skin_t - bond_t - tube_d / 2 ) + spigot_d / 2 ) - ( ( pod_d / 2 - skin_t - bond_t - tube_d / 2 ) - spigot_d / 2 )"
equation "d424 = abs(( ( close_gap / 2 + half_fw ) + -1 * spigot_edge ) - ( spigot_slot - spigot_d ) / 2)"
equation "d425 = abs(( pod_d / 2 - skin_t - bond_t - tube_d / 2 ) - spigot_d / 2)"
equation "d426 = ( ( panel_z0 ) + tube_t ) - ( panel_z0 )"
equation "d428 = panel_z0"
equation "d430 = abs(( ( close_gap / 2 + half_fw ) + -1 * spigot_edge ) - ( spigot_slot - spigot_d ) / 2)"
equation "d431 = abs(pod_d / 2 - skin_t - bond_t - tube_d / 2)"
equation "d432 = tube_t"
equation "d433 = spigot_d"
equation "d435 = panel_z0"
equation "d437 = abs(( ( close_gap / 2 + half_fw ) + -1 * spigot_edge ) + ( spigot_slot - spigot_d ) / 2)"
equation "d438 = abs(pod_d / 2 - skin_t - bond_t - tube_d / 2)"
equation "d439 = tube_t"
equation "d440 = spigot_d"
equation "d442 = panel_z0 + back_ph"
equation "d444 = abs(( close_gap / 2 ) + bolt_edge)"
equation "d445 = abs(pod_d / 2 - skin_t - bond_t - tube_d / 2)"
equation "d446 = tube_t"
equation "d447 = rivnut_d"
equation "d449 = n_len_bolt"
equation "d451 = len_bolt_pitch"
equation "d453 = panel_z0 + back_ph"
equation "d455 = abs(( close_gap / 2 ) + spigot_edge)"
equation "d456 = abs(pod_d / 2 - skin_t - bond_t - tube_d / 2)"
equation "d457 = tube_t"
equation "d458 = rivnut_d"
equation "d460 = panel_z0 + back_ph"
equation "d462 = abs(( close_gap / 2 + half_fw ) - spigot_edge)"
equation "d463 = abs(pod_d / 2 - skin_t - bond_t - tube_d / 2)"
equation "d464 = tube_t"
equation "d465 = rivnut_d"
equation "d467 = close_gap / 2 + half_fw"
equation "d469 = abs(bolt_line_y)"
equation "d470 = abs(( panel_z0 ) + bolt_edge)"
equation "d471 = tube_t"
equation "d472 = bolt_d"
equation "d474 = ( close_gap / 2 + half_fw ) + -1 * tube_w"
equation "d476 = abs(bolt_line_y)"
equation "d477 = abs(( panel_z0 ) + bolt_edge)"
equation "d478 = tube_t"
equation "d479 = access_d"
equation "d481 = n_side_jnt"
equation "d483 = side_jnt_pitch"
equation "d485 = close_gap / 2"
equation "d487 = abs(pod_d / 2 - skin_t - bond_t - tube_d / 2)"
equation "d488 = abs(( panel_z0 ) + bolt_edge)"
equation "d489 = tube_t"
equation "d490 = rivnut_d"
equation "d492 = ( close_gap / 2 ) - -1 * tube_w"
equation "d494 = abs(pod_d / 2 - skin_t - bond_t - tube_d / 2)"
equation "d495 = abs(( panel_z0 ) + bolt_edge)"
equation "d496 = tube_t"
equation "d497 = access_d"
equation "d499 = n_side_jnt"
equation "d501 = side_jnt_pitch"
equation "d503 = lead_in"
equation "d504 = panel_z0 + back_ph"
equation "d506 = abs(( close_gap / 2 ) + bolt_edge)"
equation "d507 = abs(pod_d / 2 - skin_t - bond_t - tube_d / 2)"
equation "d508 = stopw_od"
equation "d509 = stopw_id"
equation "d510 = stopw_t"
equation "d512 = ( panel_z0 + back_ph ) + stopw_t"
equation "d514 = abs(( close_gap / 2 ) + bolt_edge)"
equation "d515 = abs(pod_d / 2 - skin_t - bond_t - tube_d / 2)"
equation "d516 = rivnut_head_d"
equation "d517 = m6_d"
equation "d518 = rivnut_head_t"
equation "d520 = ( panel_z0 + back_ph ) + stopw_t"
equation "d522 = abs(( close_gap / 2 ) + bolt_edge)"
equation "d523 = abs(pod_d / 2 - skin_t - bond_t - tube_d / 2)"
equation "d524 = rivnut_body_d"
equation "d525 = m6_d"
equation "d528 = -( rivnut_len )"
equation "d530 = n_len_bolt"
equation "d532 = len_bolt_pitch"
equation "d534 = n_len_bolt"
equation "d536 = len_bolt_pitch"
equation "d538 = panel_z0 + back_ph"
equation "d540 = abs(( close_gap / 2 ) + spigot_edge)"
equation "d541 = abs(pod_d / 2 - skin_t - bond_t - tube_d / 2)"
equation "d542 = rivnut_head_d"
equation "d543 = m6_d"
equation "d544 = rivnut_head_t"
equation "d546 = panel_z0 + back_ph"
equation "d548 = abs(( close_gap / 2 ) + spigot_edge)"
equation "d549 = abs(pod_d / 2 - skin_t - bond_t - tube_d / 2)"
equation "d550 = rivnut_body_d"
equation "d551 = m6_d"
equation "d554 = -( rivnut_len )"
equation "d556 = ( panel_z0 + back_ph ) + rivnut_head_t"
equation "d558 = abs(( close_gap / 2 ) + spigot_edge)"
equation "d559 = abs(pod_d / 2 - skin_t - bond_t - tube_d / 2)"
equation "d560 = spigot_pin_d"
equation "d561 = spigot_proud - rivnut_head_t"
equation "d563 = ( panel_z0 + back_ph ) + rivnut_head_t"
equation "d565 = abs(( close_gap / 2 ) + spigot_edge)"
equation "d566 = abs(pod_d / 2 - skin_t - bond_t - tube_d / 2)"
equation "d567 = m6_d"
equation "d570 = -( spigot_thread_l )"
equation "d572 = panel_z0 + back_ph"
equation "d574 = abs(( close_gap / 2 + half_fw ) - spigot_edge)"
equation "d575 = abs(pod_d / 2 - skin_t - bond_t - tube_d / 2)"
equation "d576 = rivnut_head_d"
equation "d577 = m6_d"
equation "d578 = rivnut_head_t"
equation "d580 = panel_z0 + back_ph"
equation "d582 = abs(( close_gap / 2 + half_fw ) - spigot_edge)"
equation "d583 = abs(pod_d / 2 - skin_t - bond_t - tube_d / 2)"
equation "d584 = rivnut_body_d"
equation "d585 = m6_d"
equation "d588 = -( rivnut_len )"
equation "d590 = ( panel_z0 + back_ph ) + rivnut_head_t"
equation "d592 = abs(( close_gap / 2 + half_fw ) - spigot_edge)"
equation "d593 = abs(pod_d / 2 - skin_t - bond_t - tube_d / 2)"
equation "d594 = spigot_pin_d"
equation "d595 = spigot_proud - rivnut_head_t"
equation "d597 = ( panel_z0 + back_ph ) + rivnut_head_t"
equation "d599 = abs(( close_gap / 2 + half_fw ) - spigot_edge)"
equation "d600 = abs(pod_d / 2 - skin_t - bond_t - tube_d / 2)"
equation "d601 = m6_d"
equation "d604 = -( spigot_thread_l )"
equation "d606 = close_gap / 2"
equation "d608 = abs(pod_d / 2 - skin_t - bond_t - tube_d / 2)"
equation "d609 = abs(( panel_z0 ) + bolt_edge)"
equation "d610 = rivnut_head_d"
equation "d611 = m6_d"
equation "d614 = -( rivnut_head_t )"
equation "d616 = close_gap / 2"
equation "d618 = abs(pod_d / 2 - skin_t - bond_t - tube_d / 2)"
equation "d619 = abs(( panel_z0 ) + bolt_edge)"
equation "d620 = rivnut_body_d"
equation "d621 = m6_d"
equation "d622 = rivnut_len"
equation "d624 = n_side_jnt"
equation "d626 = side_jnt_pitch"
named bodies: "RAIL - BOTTOM", "RAIL - TOP", "STILE - CENTRE", "STILE - OUTER", "STILE - MID 1", "STILE - MID 2", "SKIN - ACP 3, OVERHANGS THE FRAME 1.62 AT THE CLOSING SEAM", "FILL - BAY 1", "FILL - BAY 2", "FILL - BAY 3", "STOP WASHER - TOP RAIL 1", "RIVNUT - TOP RAIL 1", "STOP WASHER - TOP RAIL 2", "STOP WASHER - TOP RAIL 3", "STOP WASHER - TOP RAIL 4", "RIVNUT - TOP RAIL 2", "RIVNUT - TOP RAIL 3", "RIVNUT - TOP RAIL 4", "RIVNUT - TOP RAIL SPIGOT LOW X", "SPIGOT - TOP RAIL SPIGOT LOW X", "RIVNUT - TOP RAIL SPIGOT HIGH X", "SPIGOT - TOP RAIL SPIGOT HIGH X", "RIVNUT - CENTRE STILE PIN 1", "RIVNUT - CENTRE STILE PIN 2", "RIVNUT - CENTRE STILE PIN 3"
